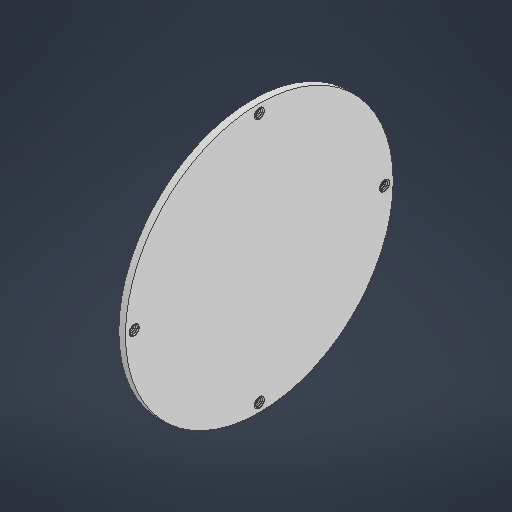
# Autodesk Inventor part: 22.10.2025-15
Saved by Autodesk Inventor 2026.1 (Build 301233020, 233B)
## iProperties
Created: 2026-01-04
Part Number: 22.10.2025-15
Material: Ogólny
Document SubType Name: Modeling
Designer: Nitro
Density: 1 g/cm^3
Appearance: Domyślna
Description: Pokrywa przeglubu obrotowego
Author: Nitro
Autodesk Inventor part; units mm, degrees
ref_plane "YZ Plane" through (0, 0, 0) normal (1, 0, 0) x (0, 1, 0)
ref_plane "XZ Plane" through (0, 0, 0) normal (0, 1, 0) x (-1, 0, 0)
ref_plane "XY Plane" through (0, 0, 0) normal (0, 0, 1) x (1, 0, 0)
sketch "Szkic1" plane through (0, 0, 0) normal (1, 0, 0) x (0, 1, 0)
  circle A0 centre (0, 0) radius 40
  dimension "d0" = 80
  constraints: 1 centre point, 1 coincident
  measures "d0" diameter of A0
extrude "Wyciągnięcie proste1" add sketch "Szkic1" along normal blind 2
sketch "Szkic2" plane through (2, 0, 0) normal (1, 0, 0) x (0, 0, -1)
  point P0 (0, 0)
  point P1 (0, 37.4)
  point P2 (-37.4, 0)
  point P3 (0, -37.4)
  point P4 (37.4, 0)
  dimension "d3" = 37.4
  dimension "d6" = 360
  constraints: 5 other
  measures "d3" distance of point (0, 0) point (0, 37.4)
hole "Otwór1" at (2, 37.4, 0) at (2, 0, 37.4) at (2, -37.4, 0) at (2, 0, -37.4) direction (-1, 0, 0) diameter 3 depth 10
thread "Gwint1" size "M3x0.5" class "6H" standard "ANSI Metric M Profile" full length
thread "Gwint2" size "M3x0.5" class "6H" standard "ANSI Metric M Profile" full length
thread "Gwint3" size "M3x0.5" class "6H" standard "ANSI Metric M Profile" full length
thread "Gwint4" size "M3x0.5" class "6H" standard "ANSI Metric M Profile" full length
sketch "Szkic4" plane through (2, -37.4, 0) normal (0, -1, 0) x (0, 0, 1)
  line L0 (1.5, 0) -> (1.5, 2)
  line L1 (1.5, 2) -> (1.1293, 2)
  line L2 (1.1293, 2) -> (1.1293, 0)
  line L3 (1.1293, 0) -> (1.5, 0)
  line L4 (0, -1.0544) -> (0, 2.5091) projected
  constraints: 8 end point
revolve "Obrót1" add sketch "Szkic4" angle 360 about axis through (2, -37.4, 0) along (-1, 0, 0) separate body
sketch "Szkic3" plane through (2, -37.4, 1.5) normal (0, 1, 0) x (-1, 0, 0)
  line L0 (-0.2918, -0.0255) -> (-0.2501, -0.0255) construction
  line L1 (0.0416, -0.3456) -> (-0.0001, -0.4257) construction
  line L2 (-0.5001, -0.4257) -> (-0.5418, -0.3456) construction
  line L3 (-0.2084, -0.0255) -> (-0.2501, 0.0546) construction
  line L4 (-0.2501, 0.0546) -> (-0.2918, -0.0255) construction
  line L5 (-0.5001, -0.4257) -> (-0.4584, -0.3456) construction
  line L6 (-0.2084, -0.0255) -> (-0.0418, -0.3456)
  line L7 (-0.5418, -0.3456) -> (-0.4584, -0.3456) construction
  arc A0 (-0.5418, -0.3456) -> (-0.5001, -0.3709) centre (-0.5001, -0.3239) ccw construction
  line L8 (0.0416, -0.3456) -> (-0.0418, -0.3456) construction
  line L9 (-0.5001, -0.4257) -> (-0.5001, -0.3456) construction
  line L10 (-0.0001, -0.4257) -> (-0.0001, -0.3456) construction
  line L11 (-0.2501, 0.0546) -> (-0.2501, -0.0002) construction
  line L12 (-0.5001, -0.3709) -> (-0.0001, -0.3709)
  arc A1 (-0.5001, -0.3709) -> (-0.4584, -0.3456) centre (-0.5001, -0.3239) ccw
  line L13 (-0.0418, -0.3456) -> (-0.0001, -0.4257) construction
  line L14 (-0.4584, -0.3456) -> (-0.2918, -0.0255)
  line L15 (-0.0001, -0.0002) -> (-0.0001, 0.0177)
  line L16 (-0.0001, 0.0177) -> (-0.0001, -0.0002)
  line L17 (-0.0001, -0.0002) -> (0.0334, -0.0002)
  arc A2 (-0.0418, -0.3456) -> (-0.0001, -0.3709) centre (-0.0001, -0.3239) ccw
  arc A3 (-0.0001, -0.3709) -> (0.0416, -0.3456) centre (-0.0001, -0.3239) ccw construction
  arc A4 (-0.2501, -0.0002) -> (-0.2918, -0.0255) centre (-0.2501, -0.0471) ccw
  arc A5 (-0.2084, -0.0255) -> (-0.2501, -0.0002) centre (-0.2501, -0.0471) ccw
  line L18 (-0.2501, -0.0002) -> (-0.2501, -0.0255) construction
  line L19 (-0.2501, -0.0255) -> (-0.2084, -0.0255) construction
  dimension "d23" = 55
  dimension "d24" = 0.08
  dimension "d25" = 0.08
  dimension "Szkic3_ThreadOffset" = 0
  dimension "Szkic3_MajorRadius" = 0.3707
  dimension "d28" = 0.5
  dimension "Szkic3_MinorRadius" = 0
  constraints: 40 end point, 12 point on circle, 10 parallel, 8 tangent, 6 centre point, 6 collinear, 2 midpoint, 2 point on line, 1 horizontal, 1 perpendicular, 3 other
  measures "d23" angle of L6 L14
  measures "d24" distance of L3.end L0.end
  measures "d25" distance of L1.end L10.end
  measures "Szkic3_ThreadOffset" distance between parallel lines of L15 L10
  measures "Szkic3_MajorRadius" distance from line of L12 L15.start
  measures "d28" distance from line of L1.end L9
  measures "Szkic3_MinorRadius" distance edge to line of A5 L17
coil "Zwój1" sketch "Szkic3" operation cut axis through (2, -37.4, 0) along (-1, 0, 0) pitch 0.5005 turns 5.994006 hand right bodies 2
sketch "Szkic6" plane through (2, 0, -37.4) normal (0, -1, 0) x (0, 0, 1)
  line L0 (1.5, 0) -> (1.5, 2)
  line L1 (1.5, 2) -> (1.1293, 2)
  line L2 (1.1293, 2) -> (1.1293, 0)
  line L3 (1.1293, 0) -> (1.5, 0)
  line L4 (0, -1.0877) -> (0, 2.7091) projected
  constraints: 8 end point
revolve "Obrót2" add sketch "Szkic6" angle 360 about axis through (2, 0, -37.4) along (-1, 0, 0) separate body
sketch "Szkic5" plane through (2, 0, -35.9) normal (0, 1, 0) x (-1, 0, 0)
  line L0 (-0.2918, -0.0255) -> (-0.2501, -0.0255) construction
  line L1 (0.0416, -0.3456) -> (-0.0001, -0.4257) construction
  line L2 (-0.5001, -0.4257) -> (-0.5418, -0.3456) construction
  line L3 (-0.2084, -0.0255) -> (-0.2501, 0.0546) construction
  line L4 (-0.2501, 0.0546) -> (-0.2918, -0.0255) construction
  line L5 (-0.5001, -0.4257) -> (-0.4584, -0.3456) construction
  line L6 (-0.2084, -0.0255) -> (-0.0418, -0.3456)
  line L7 (-0.5418, -0.3456) -> (-0.4584, -0.3456) construction
  arc A0 (-0.5418, -0.3456) -> (-0.5001, -0.3709) centre (-0.5001, -0.3239) ccw construction
  line L8 (0.0416, -0.3456) -> (-0.0418, -0.3456) construction
  line L9 (-0.5001, -0.4257) -> (-0.5001, -0.3456) construction
  line L10 (-0.0001, -0.4257) -> (-0.0001, -0.3456) construction
  line L11 (-0.2501, 0.0546) -> (-0.2501, -0.0002) construction
  line L12 (-0.5001, -0.3709) -> (-0.0001, -0.3709)
  arc A1 (-0.5001, -0.3709) -> (-0.4584, -0.3456) centre (-0.5001, -0.3239) ccw
  line L13 (-0.0418, -0.3456) -> (-0.0001, -0.4257) construction
  line L14 (-0.4584, -0.3456) -> (-0.2918, -0.0255)
  line L15 (-0.0001, -0.0002) -> (-0.0001, 0.0177)
  line L16 (-0.0001, 0.0177) -> (-0.0001, -0.0002)
  line L17 (-0.0001, -0.0002) -> (0.0334, -0.0002)
  arc A2 (-0.0418, -0.3456) -> (-0.0001, -0.3709) centre (-0.0001, -0.3239) ccw
  arc A3 (-0.0001, -0.3709) -> (0.0416, -0.3456) centre (-0.0001, -0.3239) ccw construction
  arc A4 (-0.2501, -0.0002) -> (-0.2918, -0.0255) centre (-0.2501, -0.0471) ccw
  arc A5 (-0.2084, -0.0255) -> (-0.2501, -0.0002) centre (-0.2501, -0.0471) ccw
  line L18 (-0.2501, -0.0002) -> (-0.2501, -0.0255) construction
  line L19 (-0.2501, -0.0255) -> (-0.2084, -0.0255) construction
  dimension "d41" = 55
  dimension "d42" = 0.08
  dimension "d43" = 0.08
  dimension "Szkic5_ThreadOffset" = 0
  dimension "Szkic5_MajorRadius" = 0.3707
  dimension "d46" = 0.5
  dimension "Szkic5_MinorRadius" = 0
  constraints: 40 end point, 12 point on circle, 10 parallel, 8 tangent, 6 centre point, 6 collinear, 2 midpoint, 2 point on line, 1 horizontal, 1 perpendicular, 3 other
  measures "d41" angle of L6 L14
  measures "d42" distance of L3.end L0.end
  measures "d43" distance of L1.end L10.end
  measures "Szkic5_ThreadOffset" distance between parallel lines of L15 L10
  measures "Szkic5_MajorRadius" distance from line of L12 L15.start
  measures "d46" distance from line of L1.end L9
  measures "Szkic5_MinorRadius" distance edge to line of A5 L17
coil "Zwój2" sketch "Szkic5" operation cut axis through (2, 0, -37.4) along (-1, 0, 0) pitch 0.5005 turns 5.994006 hand right bodies 3
sketch "Szkic8" plane through (2, 0, 37.4) normal (0, -1, 0) x (0, 0, 1)
  line L0 (1.5, 0) -> (1.5, 2)
  line L1 (1.5, 2) -> (1.1293, 2)
  line L2 (1.1293, 2) -> (1.1293, 0)
  line L3 (1.1293, 0) -> (1.5, 0)
  line L4 (0, -1.0877) -> (0, 2.7091) projected
  constraints: 8 end point
revolve "Obrót3" add sketch "Szkic8" angle 360 about axis through (2, 0, 37.4) along (-1, 0, 0) separate body
sketch "Szkic7" plane through (2, 0, 38.9) normal (0, 1, 0) x (-1, 0, 0)
  line L0 (-0.2918, -0.0255) -> (-0.2501, -0.0255) construction
  line L1 (0.0416, -0.3456) -> (-0.0001, -0.4257) construction
  line L2 (-0.5001, -0.4257) -> (-0.5418, -0.3456) construction
  line L3 (-0.2084, -0.0255) -> (-0.2501, 0.0546) construction
  line L4 (-0.2501, 0.0546) -> (-0.2918, -0.0255) construction
  line L5 (-0.5001, -0.4257) -> (-0.4584, -0.3456) construction
  line L6 (-0.2084, -0.0255) -> (-0.0418, -0.3456)
  line L7 (-0.5418, -0.3456) -> (-0.4584, -0.3456) construction
  arc A0 (-0.5418, -0.3456) -> (-0.5001, -0.3709) centre (-0.5001, -0.3239) ccw construction
  line L8 (0.0416, -0.3456) -> (-0.0418, -0.3456) construction
  line L9 (-0.5001, -0.4257) -> (-0.5001, -0.3456) construction
  line L10 (-0.0001, -0.4257) -> (-0.0001, -0.3456) construction
  line L11 (-0.2501, 0.0546) -> (-0.2501, -0.0002) construction
  line L12 (-0.5001, -0.3709) -> (-0.0001, -0.3709)
  arc A1 (-0.5001, -0.3709) -> (-0.4584, -0.3456) centre (-0.5001, -0.3239) ccw
  line L13 (-0.0418, -0.3456) -> (-0.0001, -0.4257) construction
  line L14 (-0.4584, -0.3456) -> (-0.2918, -0.0255)
  line L15 (-0.0001, -0.0002) -> (-0.0001, 0.0177)
  line L16 (-0.0001, 0.0177) -> (-0.0001, -0.0002)
  line L17 (-0.0001, -0.0002) -> (0.0334, -0.0002)
  arc A2 (-0.0418, -0.3456) -> (-0.0001, -0.3709) centre (-0.0001, -0.3239) ccw
  arc A3 (-0.0001, -0.3709) -> (0.0416, -0.3456) centre (-0.0001, -0.3239) ccw construction
  arc A4 (-0.2501, -0.0002) -> (-0.2918, -0.0255) centre (-0.2501, -0.0471) ccw
  arc A5 (-0.2084, -0.0255) -> (-0.2501, -0.0002) centre (-0.2501, -0.0471) ccw
  line L18 (-0.2501, -0.0002) -> (-0.2501, -0.0255) construction
  line L19 (-0.2501, -0.0255) -> (-0.2084, -0.0255) construction
  dimension "d59" = 55
  dimension "d60" = 0.08
  dimension "d61" = 0.08
  dimension "Szkic7_ThreadOffset" = 0
  dimension "Szkic7_MajorRadius" = 0.3707
  dimension "d64" = 0.5
  dimension "Szkic7_MinorRadius" = 0
  constraints: 40 end point, 12 point on circle, 10 parallel, 8 tangent, 6 centre point, 6 collinear, 2 midpoint, 2 point on line, 1 horizontal, 1 perpendicular, 3 other
  measures "d59" angle of L6 L14
  measures "d60" distance of L3.end L0.end
  measures "d61" distance of L1.end L10.end
  measures "Szkic7_ThreadOffset" distance between parallel lines of L15 L10
  measures "Szkic7_MajorRadius" distance from line of L12 L15.start
  measures "d64" distance from line of L1.end L9
  measures "Szkic7_MinorRadius" distance edge to line of A5 L17
coil "Zwój3" sketch "Szkic7" operation cut axis through (2, 0, 37.4) along (-1, 0, 0) pitch 0.5005 turns 5.994006 hand right bodies 4
sketch "Szkic10" plane through (2, 37.4, 0) normal (0, -1, 0) x (0, 0, 1)
  line L0 (1.5, 0) -> (1.5, 2)
  line L1 (1.5, 2) -> (1.1293, 2)
  line L2 (1.1293, 2) -> (1.1293, 0)
  line L3 (1.1293, 0) -> (1.5, 0)
  line L4 (0, -1.0877) -> (0, 2.7091) projected
  constraints: 8 end point
revolve "Obrót4" add sketch "Szkic10" angle 360 about axis through (2, 37.4, 0) along (-1, 0, 0) separate body
sketch "Szkic9" plane through (2, 37.4, 1.5) normal (0, 1, 0) x (-1, 0, 0)
  line L0 (-0.2918, -0.0255) -> (-0.2501, -0.0255) construction
  line L1 (0.0416, -0.3456) -> (-0.0001, -0.4257) construction
  line L2 (-0.5001, -0.4257) -> (-0.5418, -0.3456) construction
  line L3 (-0.2084, -0.0255) -> (-0.2501, 0.0546) construction
  line L4 (-0.2501, 0.0546) -> (-0.2918, -0.0255) construction
  line L5 (-0.5001, -0.4257) -> (-0.4584, -0.3456) construction
  line L6 (-0.2084, -0.0255) -> (-0.0418, -0.3456)
  line L7 (-0.5418, -0.3456) -> (-0.4584, -0.3456) construction
  arc A0 (-0.5418, -0.3456) -> (-0.5001, -0.3709) centre (-0.5001, -0.3239) ccw construction
  line L8 (0.0416, -0.3456) -> (-0.0418, -0.3456) construction
  line L9 (-0.5001, -0.4257) -> (-0.5001, -0.3456) construction
  line L10 (-0.0001, -0.4257) -> (-0.0001, -0.3456) construction
  line L11 (-0.2501, 0.0546) -> (-0.2501, -0.0002) construction
  line L12 (-0.5001, -0.3709) -> (-0.0001, -0.3709)
  arc A1 (-0.5001, -0.3709) -> (-0.4584, -0.3456) centre (-0.5001, -0.3239) ccw
  line L13 (-0.0418, -0.3456) -> (-0.0001, -0.4257) construction
  line L14 (-0.4584, -0.3456) -> (-0.2918, -0.0255)
  line L15 (-0.0001, -0.0002) -> (-0.0001, 0.0177)
  line L16 (-0.0001, 0.0177) -> (-0.0001, -0.0002)
  line L17 (-0.0001, -0.0002) -> (0.0334, -0.0002)
  arc A2 (-0.0418, -0.3456) -> (-0.0001, -0.3709) centre (-0.0001, -0.3239) ccw
  arc A3 (-0.0001, -0.3709) -> (0.0416, -0.3456) centre (-0.0001, -0.3239) ccw construction
  arc A4 (-0.2501, -0.0002) -> (-0.2918, -0.0255) centre (-0.2501, -0.0471) ccw
  arc A5 (-0.2084, -0.0255) -> (-0.2501, -0.0002) centre (-0.2501, -0.0471) ccw
  line L18 (-0.2501, -0.0002) -> (-0.2501, -0.0255) construction
  line L19 (-0.2501, -0.0255) -> (-0.2084, -0.0255) construction
  dimension "d77" = 55
  dimension "d78" = 0.08
  dimension "d79" = 0.08
  dimension "Szkic9_ThreadOffset" = 0
  dimension "Szkic9_MajorRadius" = 0.3707
  dimension "d82" = 0.5
  dimension "Szkic9_MinorRadius" = 0
  constraints: 40 end point, 12 point on circle, 10 parallel, 8 tangent, 6 centre point, 6 collinear, 2 midpoint, 2 point on line, 1 horizontal, 1 perpendicular, 3 other
  measures "d77" angle of L6 L14
  measures "d78" distance of L3.end L0.end
  measures "d79" distance of L1.end L10.end
  measures "Szkic9_ThreadOffset" distance between parallel lines of L15 L10
  measures "Szkic9_MajorRadius" distance from line of L12 L15.start
  measures "d82" distance from line of L1.end L9
  measures "Szkic9_MinorRadius" distance edge to line of A5 L17
coil "Zwój4" sketch "Szkic9" operation cut axis through (2, 37.4, 0) along (-1, 0, 0) pitch 0.5005 turns 5.994006 hand right bodies 5
equation "\"d23\" = d30"
equation "\"d24\" = 0.160083 * Szkic3_Pitch"
equation "\"d25\" = 0.160083 * Szkic3_Pitch"
equation "\"d28\" = Szkic3_Pitch"
equation "\"d41\" = d48"
equation "\"d42\" = 0.160083 * Szkic5_Pitch"
equation "\"d43\" = 0.160083 * Szkic5_Pitch"
equation "\"d46\" = Szkic5_Pitch"
equation "\"d59\" = d66"
equation "\"d60\" = 0.160083 * Szkic7_Pitch"
equation "\"d61\" = 0.160083 * Szkic7_Pitch"
equation "\"d64\" = Szkic7_Pitch"
equation "\"d77\" = d84"
equation "\"d78\" = 0.160083 * Szkic9_Pitch"
equation "\"d79\" = 0.160083 * Szkic9_Pitch"
equation "\"d82\" = Szkic9_Pitch"
equation "\"d30\" = 55deg"
equation "\"Szkic3_Pitch\" = 0.5"
equation "\"d48\" = 55deg"
equation "\"Szkic5_Pitch\" = 0.5"
equation "\"d66\" = 55deg"
equation "\"Szkic7_Pitch\" = 0.5"
equation "\"d84\" = 55deg"
equation "\"Szkic9_Pitch\" = 0.5"
